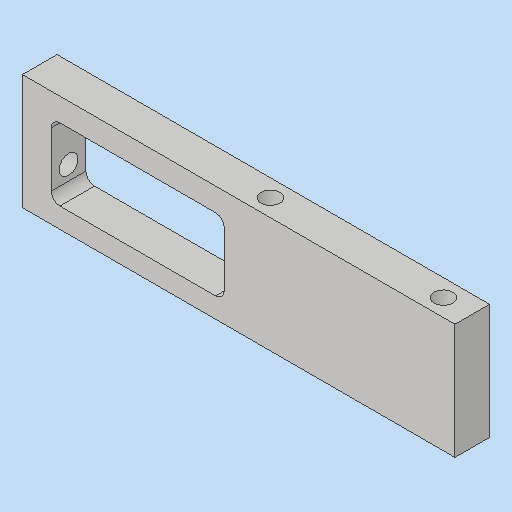
# Autodesk Inventor part: MM0948AN180_G01_105
Saved by Autodesk Inventor 2023.3 (Build 273359000, 359)
## iProperties
RuleStatus: InUse
Created: 2023-03-23
Part Number: MM0948AN180_G01_105
Material: 1.2842 90MnCrV8
Description: =<RBPARTNOTITLE2>
Document SubType Name: Modeling
Designer: ric7an
Mass: 393.964 g
Surface Area: 174.025 cm^2
Volume: 50.1865 cm^3
Density: 7.85 g/cm^3
Appearance: silber AnP
AnP_Kategorie: 1
AnP_Material: =<Material>
MaxAbmaße: 12 x 40 x 150 (FM)
AnP_TemplVers: 20200821
RBDOCUMENTTYPE: DRF
RBDOCUMENTVERSION: 00
RBDRAWINGMAINSCALE: 1:1
RBDRAWINGMISSINGSPEC: --
RBDRAWINGVOLUME: --
RBDSV1: 0850
RBGBEDGESIN1: +0,5
RBGBEDGESIN2: +0,2
RBGBEDGESOUT1: -0,3
RBGBEDGESOUT2: -0,1
RBMATERIAL: =<Material>
RBMATMEETS: --
RBMATNO: =<Part Number>
RBPARTMADEOF: 12 x 40 x 150 (FM)
RBPARTNO: SIEHE MNR
RBPARTNOTITLE1: manufactured part
RBPARTNOTITLE2: Anfertigungsteil
RBPARTSAFETYINDICATOR: --
RBSURFACE: chemically nickel-coated
RBSURFACE2: chem. vernickelt
RBZEDGESNORM: ISO13715:2002-06
RBZGENDIMCLASS: m
RBZGENDIMNORM: ISO 2768-1:1989-11
RBZGENGEOCLASS: H
RBZGENGEONORM: ISO 2768-2:1989-11
RBZSURFACENORM: ISO13D2:2002-02
RBZTOLERANCENORM: ISO 14405-1:2010-12
AnP_Kommentar_aktuell: =<Comments>
AnP_Material_aktuell: =<Material>
Author: FH/Wi
Keywords: =<RBPARTMADEOF>
Comments: =<RBSURFACE2>
Revision Number: 01
Autodesk Inventor part; units mm, degrees
ref_plane "YZ Plane" through (0, 0, 0) normal (1, 0, 0) x (0, 1, 0)
ref_plane "XZ Plane" through (0, 0, 0) normal (0, 1, 0) x (-1, 0, 0)
ref_plane "XY Plane" through (0, 0, 0) normal (0, 0, 1) x (1, 0, 0)
sketch "Skizze1" plane through (0, 0, 0) normal (0, 0, 1) x (1, 0, 0)
  line L0 (0, 0) -> (150, 0)
  line L1 (150, 0) -> (150, 40)
  line L2 (150, 40) -> (0, 40)
  line L3 (0, 40) -> (0, 0)
  line L4 (10, 32) -> (70, 32)
  line L5 (70, 32) -> (70, 7)
  line L6 (70, 7) -> (10, 7)
  line L7 (10, 7) -> (10, 32)
  dimension "d0" = 40
  dimension "d1" = 150
  dimension "d2" = 10
  dimension "d3" = 25
  dimension "d4" = 7
  dimension "d5" = 60
  constraints: 16 end point, 4 parallel, 2 horizontal, 2 perpendicular
  measures "d0" distance of L2.end L0.start
  measures "d1" distance of L1.end L2.end
  measures "d2" distance between parallel lines of L7 L3
  measures "d3" distance of L4.end L5.end
  measures "d4" distance between parallel lines of L0 L6
  measures "d5" distance of L5.end L6.end
extrude "Extrusion1" add sketch "Skizze1" along normal mid plane 12
sketch "Skizze2" plane through (0, 0, 6) normal (0, -1, 0) x (1, 0, 0)
  line L0 (-34, -6) -> (204, -6) projected
  line L1 (150, -12) -> (150, 0) projected
  point P0 (0, -6)
  point P1 (80, -6)
  point P2 (140, -6)
  dimension "d8" = 60
  dimension "d25" = 10
  constraints: 2 point on line
  measures "d8" distance of point (140, -6) point (80, -6)
  measures "d25" distance from line of L1 point (140, -6)
hole "Bohrung1" at (80, 0, 0) at (140, 0, 0) direction (0, 1, 0) diameter 6.6 end through all counterbore diameter 11 counterbore depth 6.8 clearance for "Inbusschraube ISO 4762  versenkt" size "M6" standard "ISO"
sketch "Skizze3" plane through (0, 0, 6) normal (-1, 0, 0) x (0, 0, 1)
  line L0 (-6, 48) -> (-6, -8) projected
  line L1 (-12, 40) -> (0, 40) projected
  point P0 (-6, 0)
  point P1 (-6, 15)
  dimension "d17" = 25
  constraints: 1 point on line
  measures "d17" distance from line of L1 point (-6, 15)
hole "Bohrung2" at (0, 15, 0) direction (1, 0, 0) diameter 6.6 depth 10 clearance for "Inbusschraube ISO 4762  versenkt" size "M6" standard "ISO"
fillet "Rundung1" radius 3 4 edges at (10, 7, 0) (70, 7, 0) (70, 32, 0) (10, 32, 0)
